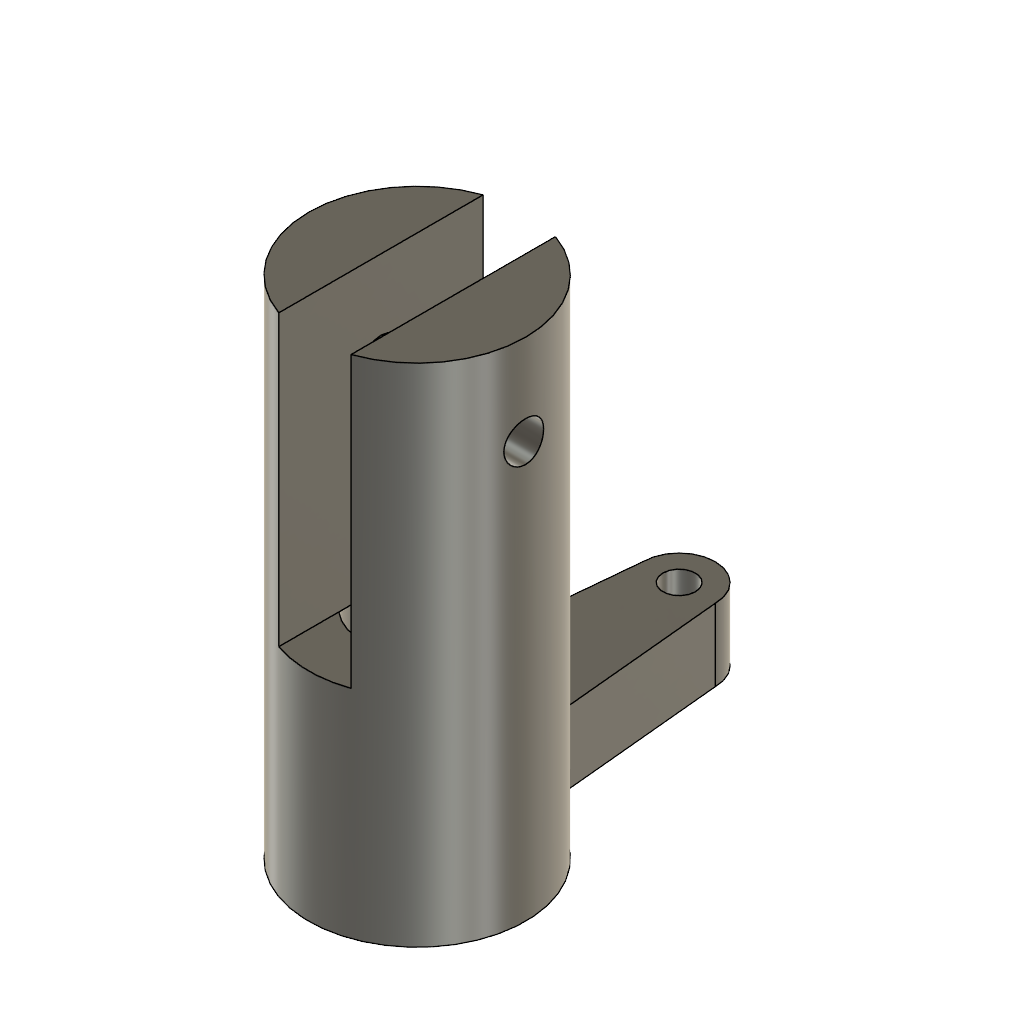
grip-r4-fit-only (Autodesk Fusion 360 design; units mm, degrees)
part number: 2026-11-01-14-44-54-387
Autodesk Fusion 360 part; units mm, degrees
ref_plane "WorkPlane1" through (0, 0, 0) normal (0, 0, 1) x (1, 0, 0)
sketch "Continuous cylindrical body OD12 assumed" plane through (0, 0, 0) normal (0, 0, 1) x (1, 0, 0)
  circle A0 centre (0, 0) radius 6
extrude "Continuous cylindrical body OD12 assumed (1)" add sketch "Continuous cylindrical body OD12 assumed" along normal blind 28
ref_plane "WorkPlane2" through (0, 0, 12) normal (0, 0, 1) x (1, 0, 0)
sketch "Blade slot - 4 mm gap assumed" plane through (0, 0, 12) normal (0, 0, 1) x (1, 0, 0)
  line L0 (-2, -8) -> (2, -8)
  line L1 (2, -8) -> (2, 8)
  line L2 (2, 8) -> (-2, 8)
  line L3 (-2, 8) -> (-2, -8)
extrude "Blade slot - 4 mm gap assumed (1)" cut sketch "Blade slot - 4 mm gap assumed" along normal blind 18
ref_plane "WorkPlane3" through (0, 0, 2) normal (0, 0, 1) x (1, 0, 0)
sketch "Rounded pitch arm - geometry assumed" plane through (0, 0, 2) normal (0, 0, 1) x (1, 0, 0)
  line L0 (-3, 4) -> (3, 4)
  line L1 (3, 4) -> (2, 14.5)
  arc A0 (2, 14.5) -> (-2, 14.5) centre (0, 14.5) ccw
  line L2 (-2, 14.5) -> (-3, 4)
extrude "Rounded pitch arm - geometry assumed (1)" add sketch "Rounded pitch arm - geometry assumed" along normal blind 4
ref_plane "WorkPlane4" through (0, 0, 0) normal (0, 0, 1) x (1, 0, 0)
sketch "Internal shoulder relief assumed" plane through (0, 0, 0) normal (0, 0, 1) x (1, 0, 0)
  circle A0 centre (0, 0) radius 2.4
extrude "Internal shoulder relief assumed (1)" cut sketch "Internal shoulder relief assumed" along normal blind 12
ref_plane "WorkPlane5" through (0, 0, 0) normal (0, 0, 1) x (1, 0, 0)
sketch "Inner radial pocket 6.15 assumed allowance" plane through (0, 0, 0) normal (0, 0, 1) x (1, 0, 0)
  circle A0 centre (0, 0) radius 3.075
extrude "Inner radial pocket 6.15 assumed allowance (1)" cut sketch "Inner radial pocket 6.15 assumed allowance" along normal blind 2.5
ref_plane "WorkPlane6" through (0, 0, 3.9) normal (0, 0, 1) x (1, 0, 0)
sketch "Outer radial and thrust access pocket" plane through (0, 0, 3.9) normal (0, 0, 1) x (1, 0, 0)
  circle A0 centre (0, 0) radius 3.075
extrude "Outer radial and thrust access pocket (1)" cut sketch "Outer radial and thrust access pocket" along normal blind 8.1
sketch "Blade bolt 2.2 mm assumed" plane through (0, 0, 0) normal (1, 0, 0) x (0, 0, -1)
  circle A0 centre (-23, 0) radius 1.1
extrude "Extrude7" cut sketch "Blade bolt 2.2 mm assumed" along normal mid plane 40
ref_plane "WorkPlane7" through (0, 0, 2) normal (0, 0, 1) x (1, 0, 0)
sketch "Pitch ball mounting 1.8 mm assumed" plane through (0, 0, 2) normal (0, 0, 1) x (1, 0, 0)
  circle A0 centre (0, 14.5) radius 0.9
extrude "Extrude8" cut sketch "Pitch ball mounting 1.8 mm assumed" along normal blind 4
named bodies: "PETG grip - fit prototype only"
